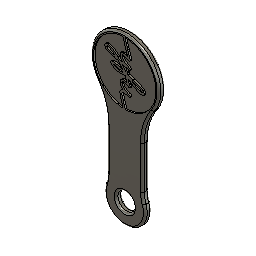
YFU-Einkaufswagenlöser (Autodesk Fusion 360 design; units mm, degrees)
Autodesk Fusion 360 part; units mm, degrees
sketch "Skizze1" plane through (0, 0, 0) normal (0, 0, 1) x (1, 0, 0)
  circle A0 centre (0, 0) radius 11.625
  line L0 (0, 0) -> (0, -38) construction
  circle A1 centre (0, -38) radius 7
  line L1 (6, -38) -> (-6, -38) construction
  line L2 (-6, -38) -> (-6, 0)
  line L3 (-6, 0) -> (6, 0) construction
  line L4 (6, 0) -> (6, -38)
  line L5 (6, -38) -> (-6, 0) construction
  line L6 (-6, -38) -> (6, 0) construction
  circle A2 centre (0, -38) radius 3
  point P0 (0, -19)
  dimension "d1" = 23.25
  dimension "d2" = 38
  dimension "d3" = 14
  dimension "d4" = 12
  dimension "d5" = 38
  dimension "d6" = 6
  constraint coincident A0.centre L0.start
  constraint vertical L0
  constraint coincident L0.end A1.centre
  constraint horizontal L1
  constraint perpendicular L1 L2
  constraint parallel L1 L3
  constraint parallel L2 L4
  constraint coincident L5 P0
  constraint coincident L6 P0
  constraint midpoint L0 P0
  constraint concentric A1 A2
  measures "d1" diameter of A0
  measures "d2" distance of A0.centre L0.end
  measures "d3" diameter of A1
  measures "d4" distance of L2.end L3.end
  measures "d5" distance of L1.end L2.end
  measures "d6" diameter of A2
extrude "Extrusion1" add sketch "Skizze1" along normal blind 2.2
fillet "Abrundung1" radius 20 2 edges at (6, -9.9569, 1.1) (-6, -9.9569, 1.1)
fillet "Abrundung2" radius 10 2 edges at (-6, -34.3944, 1.1) (6, -34.3944, 1.1)
fillet "Abrundung3" radius 0.65 18 edges at (-2.797, -36.9152, 0) (-2.797, -36.9152, 2.2) (6.1482, -33.9704, 0) (0, -45, 0) (-6.1482, -33.9704, 0) (-6, -25.1297, 0) (-6.91, -12.0396, 0) (0, 11.625, 0) (6.91, -12.0396, 0) (6, -25.1297, 0) (6.91, -12.0396, 2.2) (0, 11.625, 2.2) (-6.91, -12.0396, 2.2) (-6, -25.1297, 2.2) (-6.1482, -33.9704, 2.2) (0, -45, 2.2) (6.1482, -33.9704, 2.2) (6, -25.1297, 2.2)
sketch "Skizze2" plane through (0, 0, 2.2) normal (0, 0, 1) x (1, 0, 0)
  spline S0 degree 3 poles (-10.5033, 1.5521) (-10.1528, 3.8406) (-9.1449, 5.8129) (-7.4734, 7.4809) knots 0 0 0 0 1 1 1 1
  spline S1 degree 3 poles (-7.4734, 7.4809) (-5.8523, 9.0987) (-4.0263, 10.0374) (-1.7058, 10.4458) knots 0 0 0 0 1 1 1 1
  spline S2 degree 3 poles (-1.7058, 10.4458) (-0.9378, 10.5809) (-0.7066, 10.5692) (-0.6295, 10.3913) knots 0 0 0 0 1 1 1 1
  spline S3 degree 3 poles (-0.6295, 10.3913) (-0.4704, 10.0242) (0.9325, 5.5157) (0.9027, 5.4675) knots 0 0 0 0 1 1 1 1
  spline S4 degree 3 poles (0.9027, 5.4675) (0.8842, 5.4377) (0.6417, 5.4858) (0.3637, 5.5744) knots 0 0 0 0 1 1 1 1
  spline S5 degree 3 poles (0.3637, 5.5744) (-0.0376, 5.7023) (-0.2457, 5.731) (-0.646, 5.7135) knots 0 0 0 0 1 1 1 1
  spline S6 degree 3 poles (-0.646, 5.7135) (-1.1144, 5.693) (-1.1653, 5.6764) (-1.3616, 5.4806) knots 0 0 0 0 1 1 1 1
  spline S7 degree 3 poles (-1.3616, 5.4806) (-1.5554, 5.2872) (-1.575, 5.2295) (-1.5974, 4.7865) knots 0 0 0 0 1 1 1 1
  spline S8 degree 3 poles (-1.5974, 4.7865) (-1.6181, 4.3785) (-1.5968, 4.2494) (-1.462, 3.9572) knots 0 0 0 0 1 1 1 1
  spline S9 degree 3 poles (-1.462, 3.9572) (-1.3741, 3.7669) (-1.1921, 3.4804) (-1.0575, 3.3207) knots 0 0 0 0 1 1 1 1
  spline S10 degree 3 poles (-1.0575, 3.3207) (-0.9166, 3.1535) (-0.8445, 3.0197) (-0.8876, 3.0053) knots 0 0 0 0 1 1 1 1
  spline S11 degree 3 poles (-0.8876, 3.0053) (-0.9287, 2.9917) (-1.159, 3.0334) (-1.3993, 3.098) knots 0 0 0 0 1 1 1 1
  spline S12 degree 3 poles (-1.3993, 3.098) (-1.7925, 3.2038) (-1.8915, 3.2678) (-2.3902, 3.7386) knots 0 0 0 0 1 1 1 1
  spline S13 degree 3 poles (-2.3902, 3.7386) (-3.7693, 5.0406) (-4.966, 5.7252) (-5.862, 5.7247) knots 0 0 0 0 1 1 1 1
  spline S14 degree 3 poles (-5.862, 5.7247) (-6.5411, 5.7242) (-6.8964, 5.3636) (-6.8002, 4.7721) knots 0 0 0 0 1 1 1 1
  spline S15 degree 3 poles (-6.8002, 4.7721) (-6.6703, 3.9732) (-5.9098, 3.5452) (-3.6346, 2.9902) knots 0 0 0 0 1 1 1 1
  line L0 (-3.6346, 2.9902) -> (-2.2924, 2.6628)
  line L1 (-2.2924, 2.6628) -> (-1.8961, 2.2472)
  spline S16 degree 3 poles (-1.8961, 2.2472) (-1.2636, 1.5837) (-0.7353, 0.9112) (-0.7998, 0.8515) knots 0 0 0 0 1 1 1 1
  spline S17 degree 3 poles (-0.7998, 0.8515) (-0.8322, 0.8215) (-1.1959, 0.8969) (-1.6081, 1.0189) knots 0 0 0 0 1 1 1 1
  spline S18 degree 3 poles (-1.6081, 1.0189) (-3.5379, 1.5902) (-4.6198, 1.6409) (-4.7704, 1.1673) knots 0 0 0 0 1 1 1 1
  spline S19 degree 3 poles (-4.7704, 1.1673) (-4.9604, 0.5698) (-4.1022, -0.1345) (-2.6696, -0.5565) knots 0 0 0 0 1 1 1 1
  spline S20 degree 3 poles (-2.6696, -0.5565) (-1.9152, -0.7788) (-0.8863, -0.8349) (-0.3699, -0.6819) knots 0 0 0 0 1 1 1 1
  spline S21 degree 3 poles (-0.3699, -0.6819) (0.2499, -0.4983) (0.2219, -0.4822) (0.357, -1.1032) knots 0 0 0 0 1 1 1 1
  spline S22 degree 3 poles (0.357, -1.1032) (0.4231, -1.4067) (0.5242, -1.7964) (0.5816, -1.9691) knots 0 0 0 0 1 1 1 1
  spline S23 degree 3 poles (0.5816, -1.9691) (0.6391, -2.1419) (0.6693, -2.3) (0.6487, -2.3206) knots 0 0 0 0 1 1 1 1
  spline S24 degree 3 poles (0.6487, -2.3206) (0.6281, -2.3411) (0.4399, -2.3099) (0.2305, -2.2513) knots 0 0 0 0 1 1 1 1
  spline S25 degree 3 poles (0.2305, -2.2513) (-0.5621, -2.0293) (-1.1647, -2.1532) (-1.4656, -2.5999) knots 0 0 0 0 1 1 1 1
  spline S26 degree 3 poles (-1.4656, -2.5999) (-1.601, -2.8011) (-1.6163, -2.8882) (-1.5965, -3.3479) knots 0 0 0 0 1 1 1 1
  spline S27 degree 3 poles (-1.5965, -3.3479) (-1.5696, -3.9746) (-1.4152, -4.3304) (-0.9494, -4.839) knots 0 0 0 0 1 1 1 1
  spline S28 degree 3 poles (-0.9494, -4.839) (-0.774, -5.0305) (-0.6306, -5.2039) (-0.6306, -5.2243) knots 0 0 0 0 1 1 1 1
  spline S29 degree 3 poles (-0.6306, -5.2243) (-0.6306, -5.2448) (-0.7502, -5.2936) (-0.8965, -5.3329) knots 0 0 0 0 1 1 1 1
  spline S30 degree 3 poles (-0.8965, -5.3329) (-1.0427, -5.3722) (-1.2684, -5.5013) (-1.3979, -5.6198) knots 0 0 0 0 1 1 1 1
  spline S31 degree 3 poles (-1.3979, -5.6198) (-1.6136, -5.8171) (-1.6354, -5.8701) (-1.6574, -6.25) knots 0 0 0 0 1 1 1 1
  spline S32 degree 3 poles (-1.6574, -6.25) (-1.6842, -6.7123) (-1.4917, -7.4945) (-0.8791, -9.4137) knots 0 0 0 0 1 1 1 1
  spline S33 degree 3 poles (-0.8791, -9.4137) (-0.6741, -10.056) (-0.5653, -10.4935) (-0.6023, -10.5272) knots 0 0 0 0 1 1 1 1
  spline S34 degree 3 poles (-0.6023, -10.5272) (-0.6902, -10.6076) (-1.662, -10.4904) (-2.4376, -10.306) knots 0 0 0 0 1 1 1 1
  spline S35 degree 3 poles (-2.4376, -10.306) (-4.4197, -9.8347) (-6.0019, -8.9472) (-7.4774, -7.4792) knots 0 0 0 0 1 1 1 1
  spline S36 degree 3 poles (-7.4774, -7.4792) (-9.0145, -5.9499) (-9.9528, -4.2259) (-10.4098, -2.0912) knots 0 0 0 0 1 1 1 1
  spline S37 degree 3 poles (-10.4098, -2.0912) (-10.5887, -1.2553) (-10.6382, 0.6718) (-10.5033, 1.5521) knots 0 0 0 0 1 1 1 1
  spline S38 degree 3 poles (-6.0043, 5.0521) (-5.6966, 5.1699) (-4.6934, 4.7348) (-3.9256, 4.1504) knots 0 0 0 0 1 1 1 1
  spline S39 degree 3 poles (-3.9256, 4.1504) (-3.1644, 3.571) (-3.2537, 3.5349) (-4.5072, 3.9149) knots 0 0 0 0 1 1 1 1
  spline S40 degree 3 poles (-4.5072, 3.9149) (-5.2149, 4.1295) (-5.7283, 4.3623) (-5.9582, 4.5727) knots 0 0 0 0 1 1 1 1
  spline S41 degree 3 poles (-5.9582, 4.5727) (-6.1266, 4.7269) (-6.1524, 4.9953) (-6.0043, 5.0521) knots 0 0 0 0 1 1 1 1
  spline S42 degree 3 poles (-3.7885, 0.7956) (-3.7056, 0.8784) (-1.0857, 0.2309) (-0.8238, 0.0629) knots 0 0 0 0 1 1 1 1
  spline S43 degree 3 poles (-0.8238, 0.0629) (-0.7402, 0.0092) (-0.7405, -0.0064) (-0.826, -0.0625) knots 0 0 0 0 1 1 1 1
  spline S44 degree 3 poles (-0.826, -0.0625) (-1.1352, -0.265) (-2.5574, 0.022) (-3.4491, 0.4669) knots 0 0 0 0 1 1 1 1
  spline S45 degree 3 poles (-3.4491, 0.4669) (-3.8015, 0.6427) (-3.8727, 0.7116) (-3.7885, 0.7956) knots 0 0 0 0 1 1 1 1
  spline S46 degree 3 poles (-0.8861, -6.0748) (-0.6864, -5.8945) (0.0147, -5.9197) (0.8864, -6.1385) knots 0 0 0 0 1 1 1 1
  spline S47 degree 3 poles (0.8864, -6.1385) (1.6494, -6.3301) (1.8242, -6.3185) (1.8861, -6.0725) knots 0 0 0 0 1 1 1 1
  spline S48 degree 3 poles (1.8861, -6.0725) (1.9422, -5.8496) (1.7868, -5.6991) (1.3212, -5.5254) knots 0 0 0 0 1 1 1 1
  spline S49 degree 3 poles (1.3212, -5.5254) (0.0512, -5.0514) (-0.9539, -4.056) (-0.9557, -3.2703) knots 0 0 0 0 1 1 1 1
  spline S50 degree 3 poles (-0.9557, -3.2703) (-0.9565, -2.9578) (-0.7938, -2.795) (-0.4809, -2.795) knots 0 0 0 0 1 1 1 1
  spline S51 degree 3 poles (-0.4809, -2.795) (-0.2386, -2.795) (0.5756, -3.0693) (1.0649, -3.3158) knots 0 0 0 0 1 1 1 1
  spline S52 degree 3 poles (1.0649, -3.3158) (1.5475, -3.559) (1.7577, -3.5672) (1.8583, -3.3468) knots 0 0 0 0 1 1 1 1
  spline S53 degree 3 poles (1.8583, -3.3468) (1.924, -3.2028) (1.8969, -3.1144) (1.634, -2.6151) knots 0 0 0 0 1 1 1 1
  spline S54 degree 3 poles (1.634, -2.6151) (1.29, -1.9614) (1.031, -1.2409) (1.1114, -1.1607) knots 0 0 0 0 1 1 1 1
  spline S55 degree 3 poles (1.1114, -1.1607) (1.1417, -1.1305) (1.4293, -1.2975) (1.7506, -1.5319) knots 0 0 0 0 1 1 1 1
  spline S56 degree 3 poles (1.7506, -1.5319) (2.874, -2.3516) (4.2521, -3.1185) (5.1301, -3.4126) knots 0 0 0 0 1 1 1 1
  spline S57 degree 3 poles (5.1301, -3.4126) (5.9218, -3.6779) (6.3774, -3.6152) (6.5677, -3.2152) knots 0 0 0 0 1 1 1 1
  spline S58 degree 3 poles (6.5677, -3.2152) (6.769, -2.7918) (6.6487, -2.4444) (6.1439, -1.9915) knots 0 0 0 0 1 1 1 1
  spline S59 degree 3 poles (6.1439, -1.9915) (5.6694, -1.5657) (4.7908, -1.1557) (2.9213, -0.4876) knots 0 0 0 0 1 1 1 1
  spline S60 degree 3 poles (2.9213, -0.4876) (2.061, -0.1801) (1.275, 0.1038) (1.1744, 0.1434) knots 0 0 0 0 1 1 1 1
  spline S61 degree 3 poles (1.1744, 0.1434) (0.9982, 0.2128) (0.9932, 0.2274) (1.0339, 0.553) knots 0 0 0 0 1 1 1 1
  spline S62 degree 3 poles (1.0339, 0.553) (1.0675, 0.8209) (1.0538, 0.9129) (0.9676, 0.9989) knots 0 0 0 0 1 1 1 1
  spline S63 degree 3 poles (0.9676, 0.9989) (0.8043, 1.1619) (0.6351, 1.1301) (0.457, 0.903) knots 0 0 0 0 1 1 1 1
  line L2 (0.457, 0.903) -> (0.2968, 0.6988)
  line L3 (0.2968, 0.6988) -> (0.1663, 0.8542)
  spline S64 degree 3 poles (0.1663, 0.8542) (-0.2998, 1.4091) (-0.8261, 2.0959) (-0.8261, 2.1495) knots 0 0 0 0 1 1 1 1
  spline S65 degree 3 poles (-0.8261, 2.1495) (-0.8261, 2.2398) (-0.8411, 2.2428) (0.392, 1.9123) knots 0 0 0 0 1 1 1 1
  spline S66 degree 3 poles (0.392, 1.9123) (1.6018, 1.588) (1.8152, 1.5801) (1.8848, 1.857) knots 0 0 0 0 1 1 1 1
  spline S67 degree 3 poles (1.8848, 1.857) (1.9425, 2.0863) (1.8472, 2.1729) (1.1356, 2.5387) knots 0 0 0 0 1 1 1 1
  spline S68 degree 3 poles (1.1356, 2.5387) (-0.0871, 3.1671) (-0.8665, 3.933) (-0.9393, 4.5777) knots 0 0 0 0 1 1 1 1
  spline S69 degree 3 poles (-0.9393, 4.5777) (-0.9609, 4.7693) (-0.9437, 4.9139) (-0.8917, 4.9764) knots 0 0 0 0 1 1 1 1
  spline S70 degree 3 poles (-0.8917, 4.9764) (-0.7063, 5.1993) (0.1479, 5.0127) (1.0783, 4.5461) knots 0 0 0 0 1 1 1 1
  spline S71 degree 3 poles (1.0783, 4.5461) (1.5402, 4.3145) (1.7588, 4.3049) (1.8534, 4.5121) knots 0 0 0 0 1 1 1 1
  spline S72 degree 3 poles (1.8534, 4.5121) (1.9121, 4.6405) (1.7853, 5.098) (1.0653, 7.3575) knots 0 0 0 0 1 1 1 1
  spline S73 degree 3 poles (1.0653, 7.3575) (0.5934, 8.8383) (0.1769, 10.1477) (0.1398, 10.2673) knots 0 0 0 0 1 1 1 1
  spline S74 degree 3 poles (0.1398, 10.2673) (0.0361, 10.6011) (0.101, 10.6227) (0.9537, 10.5389) knots 0 0 0 0 1 1 1 1
  spline S75 degree 3 poles (0.9537, 10.5389) (3.6317, 10.2757) (5.8072, 9.2204) (7.6787, 7.277) knots 0 0 0 0 1 1 1 1
  spline S76 degree 3 poles (7.6787, 7.277) (9.1937, 5.7038) (10.122, 3.8436) (10.4818, 1.66) knots 0 0 0 0 1 1 1 1
  spline S77 degree 3 poles (10.4818, 1.66) (10.6245, 0.7945) (10.6099, -0.9093) (10.4521, -1.8307) knots 0 0 0 0 1 1 1 1
  spline S78 degree 3 poles (10.4521, -1.8307) (9.7041, -6.1971) (6.1688, -9.7165) (1.8134, -10.4307) knots 0 0 0 0 1 1 1 1
  spline S79 degree 3 poles (1.8134, -10.4307) (0.8283, -10.5922) (0.3166, -10.6224) (0.2362, -10.5236) knots 0 0 0 0 1 1 1 1
  spline S80 degree 3 poles (0.2362, -10.5236) (0.0663, -10.3148) (-1.0208, -6.6927) (-1.0213, -6.3334) knots 0 0 0 0 1 1 1 1
  spline S81 degree 3 poles (-1.0213, -6.3334) (-1.0213, -6.2585) (-0.9606, -6.1421) (-0.8861, -6.0748) knots 0 0 0 0 1 1 1 1
  spline S82 degree 3 poles (2.5139, -1.0726) (2.8094, -1.1579) (4.268, -1.7013) (4.632, -1.8617) knots 0 0 0 0 1 1 1 1
  spline S83 degree 3 poles (4.632, -1.8617) (5.1094, -2.0721) (5.8604, -2.5681) (5.9145, -2.7089) knots 0 0 0 0 1 1 1 1
  spline S84 degree 3 poles (5.9145, -2.7089) (5.9373, -2.7682) (5.9281, -2.8447) (5.8939, -2.8787) knots 0 0 0 0 1 1 1 1
  spline S85 degree 3 poles (5.8939, -2.8787) (5.7345, -3.0378) (4.127, -2.3053) (2.9928, -1.5568) knots 0 0 0 0 1 1 1 1
  spline S86 degree 3 poles (2.9928, -1.5568) (2.3828, -1.1542) (2.2174, -0.987) (2.5139, -1.0726) knots 0 0 0 0 1 1 1 1
  circle A0 centre (0, -38) radius 3.65
  arc A1 (9.0229, -6.248) -> (5.35, -18.0039) centre (26, -18.0039) ccw
  arc A2 (9.0229, -6.248) -> (-9.0229, -6.248) centre (0, 0) ccw
  arc A3 (-5.35, -18.0039) -> (-9.0229, -6.248) centre (-26, -18.0039) ccw
  line L4 (-5.35, -18.0039) -> (-5.35, -32.2554)
  arc A4 (-5.9765, -35.8542) -> (-5.35, -32.2554) centre (-16, -32.2554) ccw
  arc A5 (-5.9765, -35.8542) -> (5.9765, -35.8542) centre (0, -38) ccw
  arc A6 (5.35, -32.2554) -> (5.9765, -35.8542) centre (16, -32.2554) ccw
  line L5 (5.35, -32.2554) -> (5.35, -18.0039)
extrude "Extrusion2" cut sketch "Skizze2" against normal blind 0.5 contours S0 S1 S2 S3 S4 S5 S6 S7 S8 S9 S10 S11 S12 S13 S14 S15 L0 L1 S16 S17 S18 S19 S20 S21 S22 S23 S24 S25 S26 S27 S28 S29 S30 S31 S32 S33 S34 S35 S36 S37 | S38 S39 S40 S41 | S42 S43 S44 S45 | S46 S47 S48 S49 S50 S51 S52 S53 S54 S55 S56 S57 S58 S59 S60 S61 S62 S63 L2 L3 S64 S65 S66 S67 S68 S69 S70 S71 S72 S73 S74 S75 S76 S77 S78 S79 S80 S81 | S82 S83 S84 S85 S86
sketch "Skizze3" plane through (0, 0, 0) normal (0, 0, -1) x (-1, 0, 0)
  spline S0 degree 3 poles (-10.5497, 1.559) (-10.1976, 3.8576) (-9.1852, 5.8385) (-7.5064, 7.5139) knots 0 0 0 0 1 1 1 1
  spline S1 degree 3 poles (-7.5064, 7.5139) (-5.8781, 9.1389) (-4.0441, 10.0817) (-1.7134, 10.4918) knots 0 0 0 0 1 1 1 1
  spline S2 degree 3 poles (-1.7134, 10.4918) (-0.9419, 10.6276) (-0.7097, 10.6158) (-0.6323, 10.4372) knots 0 0 0 0 1 1 1 1
  spline S3 degree 3 poles (-0.6323, 10.4372) (-0.4725, 10.0685) (0.9366, 5.54) (0.9067, 5.4916) knots 0 0 0 0 1 1 1 1
  spline S4 degree 3 poles (0.9067, 5.4916) (0.8881, 5.4617) (0.6445, 5.51) (0.3653, 5.599) knots 0 0 0 0 1 1 1 1
  spline S5 degree 3 poles (0.3653, 5.599) (-0.0378, 5.7274) (-0.2467, 5.7563) (-0.6489, 5.7387) knots 0 0 0 0 1 1 1 1
  spline S6 degree 3 poles (-0.6489, 5.7387) (-1.1193, 5.7182) (-1.1705, 5.7015) (-1.3677, 5.5047) knots 0 0 0 0 1 1 1 1
  spline S7 degree 3 poles (-1.3677, 5.5047) (-1.5623, 5.3105) (-1.5819, 5.2526) (-1.6045, 4.8076) knots 0 0 0 0 1 1 1 1
  spline S8 degree 3 poles (-1.6045, 4.8076) (-1.6252, 4.3978) (-1.6038, 4.2682) (-1.4685, 3.9747) knots 0 0 0 0 1 1 1 1
  spline S9 degree 3 poles (-1.4685, 3.9747) (-1.3802, 3.7835) (-1.1974, 3.4958) (-1.0622, 3.3353) knots 0 0 0 0 1 1 1 1
  spline S10 degree 3 poles (-1.0622, 3.3353) (-0.9207, 3.1674) (-0.8483, 3.033) (-0.8915, 3.0186) knots 0 0 0 0 1 1 1 1
  spline S11 degree 3 poles (-0.8915, 3.0186) (-0.9328, 3.0049) (-1.1641, 3.0468) (-1.4055, 3.1117) knots 0 0 0 0 1 1 1 1
  spline S12 degree 3 poles (-1.4055, 3.1117) (-1.8004, 3.2179) (-1.8999, 3.2822) (-2.4007, 3.7551) knots 0 0 0 0 1 1 1 1
  spline S13 degree 3 poles (-2.4007, 3.7551) (-3.7859, 5.0628) (-4.9879, 5.7504) (-5.8878, 5.7499) knots 0 0 0 0 1 1 1 1
  spline S14 degree 3 poles (-5.8878, 5.7499) (-6.57, 5.7495) (-6.9268, 5.3872) (-6.8302, 4.7932) knots 0 0 0 0 1 1 1 1
  spline S15 degree 3 poles (-6.8302, 4.7932) (-6.6997, 3.9908) (-5.9359, 3.5608) (-3.6506, 3.0033) knots 0 0 0 0 1 1 1 1
  line L0 (-3.6506, 3.0033) -> (-2.3025, 2.6745)
  line L1 (-2.3025, 2.6745) -> (-1.9045, 2.2571)
  spline S16 degree 3 poles (-1.9045, 2.2571) (-1.2692, 1.5907) (-0.7385, 0.9152) (-0.8034, 0.8552) knots 0 0 0 0 1 1 1 1
  spline S17 degree 3 poles (-0.8034, 0.8552) (-0.8359, 0.8252) (-1.2012, 0.9008) (-1.6152, 1.0234) knots 0 0 0 0 1 1 1 1
  spline S18 degree 3 poles (-1.6152, 1.0234) (-3.5535, 1.5972) (-4.6402, 1.6482) (-4.7915, 1.1724) knots 0 0 0 0 1 1 1 1
  spline S19 degree 3 poles (-4.7915, 1.1724) (-4.9823, 0.5723) (-4.1203, -0.135) (-2.6814, -0.559) knots 0 0 0 0 1 1 1 1
  spline S20 degree 3 poles (-2.6814, -0.559) (-1.9236, -0.7822) (-0.8902, -0.8386) (-0.3715, -0.685) knots 0 0 0 0 1 1 1 1
  spline S21 degree 3 poles (-0.3715, -0.685) (0.251, -0.5005) (0.2229, -0.4843) (0.3586, -1.1081) knots 0 0 0 0 1 1 1 1
  spline S22 degree 3 poles (0.3586, -1.1081) (0.425, -1.4129) (0.5265, -1.8044) (0.5842, -1.9778) knots 0 0 0 0 1 1 1 1
  spline S23 degree 3 poles (0.5842, -1.9778) (0.6419, -2.1513) (0.6723, -2.3102) (0.6516, -2.3308) knots 0 0 0 0 1 1 1 1
  spline S24 degree 3 poles (0.6516, -2.3308) (0.6309, -2.3514) (0.4418, -2.3201) (0.2315, -2.2612) knots 0 0 0 0 1 1 1 1
  spline S25 degree 3 poles (0.2315, -2.2612) (-0.5646, -2.0383) (-1.1698, -2.1627) (-1.472, -2.6114) knots 0 0 0 0 1 1 1 1
  spline S26 degree 3 poles (-1.472, -2.6114) (-1.6081, -2.8134) (-1.6234, -2.9009) (-1.6036, -3.3626) knots 0 0 0 0 1 1 1 1
  spline S27 degree 3 poles (-1.6036, -3.3626) (-1.5765, -3.9921) (-1.4215, -4.3495) (-0.9536, -4.8603) knots 0 0 0 0 1 1 1 1
  spline S28 degree 3 poles (-0.9536, -4.8603) (-0.7774, -5.0527) (-0.6333, -5.2268) (-0.6333, -5.2474) knots 0 0 0 0 1 1 1 1
  spline S29 degree 3 poles (-0.6333, -5.2474) (-0.6333, -5.2679) (-0.7535, -5.317) (-0.9004, -5.3564) knots 0 0 0 0 1 1 1 1
  spline S30 degree 3 poles (-0.9004, -5.3564) (-1.0473, -5.3959) (-1.2739, -5.5256) (-1.4041, -5.6446) knots 0 0 0 0 1 1 1 1
  spline S31 degree 3 poles (-1.4041, -5.6446) (-1.6207, -5.8427) (-1.6427, -5.896) (-1.6648, -6.2776) knots 0 0 0 0 1 1 1 1
  spline S32 degree 3 poles (-1.6648, -6.2776) (-1.6916, -6.7419) (-1.4983, -7.5275) (-0.883, -9.4552) knots 0 0 0 0 1 1 1 1
  spline S33 degree 3 poles (-0.883, -9.4552) (-0.6771, -10.1004) (-0.5678, -10.5398) (-0.6049, -10.5737) knots 0 0 0 0 1 1 1 1
  spline S34 degree 3 poles (-0.6049, -10.5737) (-0.6932, -10.6544) (-1.6693, -10.5367) (-2.4483, -10.3515) knots 0 0 0 0 1 1 1 1
  spline S35 degree 3 poles (-2.4483, -10.3515) (-4.4392, -9.878) (-6.0284, -8.9867) (-7.5104, -7.5122) knots 0 0 0 0 1 1 1 1
  spline S36 degree 3 poles (-7.5104, -7.5122) (-9.0543, -5.9761) (-9.9967, -4.2445) (-10.4557, -2.1004) knots 0 0 0 0 1 1 1 1
  spline S37 degree 3 poles (-10.4557, -2.1004) (-10.6354, -1.2608) (-10.6851, 0.6748) (-10.5497, 1.559) knots 0 0 0 0 1 1 1 1
  spline S38 degree 3 poles (-6.0308, 5.0744) (-5.7217, 5.1927) (-4.7141, 4.7557) (-3.9429, 4.1687) knots 0 0 0 0 1 1 1 1
  spline S39 degree 3 poles (-3.9429, 4.1687) (-3.1783, 3.5868) (-3.268, 3.5505) (-4.527, 3.9322) knots 0 0 0 0 1 1 1 1
  spline S40 degree 3 poles (-4.527, 3.9322) (-5.2379, 4.1477) (-5.7536, 4.3815) (-5.9845, 4.5929) knots 0 0 0 0 1 1 1 1
  spline S41 degree 3 poles (-5.9845, 4.5929) (-6.1536, 4.7477) (-6.1795, 5.0174) (-6.0308, 5.0744) knots 0 0 0 0 1 1 1 1
  spline S42 degree 3 poles (-3.8052, 0.7991) (-3.7219, 0.8823) (-1.0905, 0.2319) (-0.8274, 0.0631) knots 0 0 0 0 1 1 1 1
  spline S43 degree 3 poles (-0.8274, 0.0631) (-0.7434, 0.0092) (-0.7437, -0.0064) (-0.8297, -0.0627) knots 0 0 0 0 1 1 1 1
  spline S44 degree 3 poles (-0.8297, -0.0627) (-1.1402, -0.2662) (-2.5687, 0.0221) (-3.4643, 0.4689) knots 0 0 0 0 1 1 1 1
  spline S45 degree 3 poles (-3.4643, 0.4689) (-3.8183, 0.6455) (-3.8898, 0.7148) (-3.8052, 0.7991) knots 0 0 0 0 1 1 1 1
  spline S46 degree 3 poles (-0.89, -6.1016) (-0.6894, -5.9205) (0.0148, -5.9458) (0.8903, -6.1656) knots 0 0 0 0 1 1 1 1
  spline S47 degree 3 poles (0.8903, -6.1656) (1.6567, -6.358) (1.8323, -6.3464) (1.8944, -6.0993) knots 0 0 0 0 1 1 1 1
  spline S48 degree 3 poles (1.8944, -6.0993) (1.9507, -5.8755) (1.7947, -5.7242) (1.327, -5.5497) knots 0 0 0 0 1 1 1 1
  spline S49 degree 3 poles (1.327, -5.5497) (0.0514, -5.0737) (-0.9581, -4.0738) (-0.96, -3.2847) knots 0 0 0 0 1 1 1 1
  spline S50 degree 3 poles (-0.96, -3.2847) (-0.9607, -2.9708) (-0.7973, -2.8074) (-0.483, -2.8074) knots 0 0 0 0 1 1 1 1
  spline S51 degree 3 poles (-0.483, -2.8074) (-0.2396, -2.8074) (0.5781, -3.0829) (1.0696, -3.3305) knots 0 0 0 0 1 1 1 1
  spline S52 degree 3 poles (1.0696, -3.3305) (1.5544, -3.5747) (1.7654, -3.5829) (1.8665, -3.3615) knots 0 0 0 0 1 1 1 1
  spline S53 degree 3 poles (1.8665, -3.3615) (1.9325, -3.217) (1.9053, -3.1282) (1.6412, -2.6266) knots 0 0 0 0 1 1 1 1
  spline S54 degree 3 poles (1.6412, -2.6266) (1.2956, -1.9701) (1.0356, -1.2464) (1.1163, -1.1659) knots 0 0 0 0 1 1 1 1
  spline S55 degree 3 poles (1.1163, -1.1659) (1.1468, -1.1355) (1.4357, -1.3033) (1.7583, -1.5387) knots 0 0 0 0 1 1 1 1
  spline S56 degree 3 poles (1.7583, -1.5387) (2.8867, -2.362) (4.2709, -3.1323) (5.1528, -3.4277) knots 0 0 0 0 1 1 1 1
  spline S57 degree 3 poles (5.1528, -3.4277) (5.9479, -3.6941) (6.4056, -3.6312) (6.5967, -3.2294) knots 0 0 0 0 1 1 1 1
  spline S58 degree 3 poles (6.5967, -3.2294) (6.7988, -2.8042) (6.678, -2.4552) (6.1711, -2.0003) knots 0 0 0 0 1 1 1 1
  spline S59 degree 3 poles (6.1711, -2.0003) (5.6944, -1.5726) (4.8119, -1.1608) (2.9342, -0.4897) knots 0 0 0 0 1 1 1 1
  spline S60 degree 3 poles (2.9342, -0.4897) (2.0701, -0.1809) (1.2806, 0.1042) (1.1796, 0.144) knots 0 0 0 0 1 1 1 1
  spline S61 degree 3 poles (1.1796, 0.144) (1.0026, 0.2137) (0.9976, 0.2284) (1.0385, 0.5554) knots 0 0 0 0 1 1 1 1
  spline S62 degree 3 poles (1.0385, 0.5554) (1.0722, 0.8245) (1.0585, 0.9169) (0.9719, 1.0033) knots 0 0 0 0 1 1 1 1
  spline S63 degree 3 poles (0.9719, 1.0033) (0.8078, 1.167) (0.638, 1.1351) (0.459, 0.907) knots 0 0 0 0 1 1 1 1
  line L2 (0.459, 0.907) -> (0.2982, 0.7019)
  line L3 (0.2982, 0.7019) -> (0.167, 0.858)
  spline S64 degree 3 poles (0.167, 0.858) (-0.3012, 1.4153) (-0.8297, 2.1051) (-0.8297, 2.159) knots 0 0 0 0 1 1 1 1
  spline S65 degree 3 poles (-0.8297, 2.159) (-0.8297, 2.2497) (-0.8448, 2.2527) (0.3937, 1.9207) knots 0 0 0 0 1 1 1 1
  spline S66 degree 3 poles (0.3937, 1.9207) (1.6088, 1.5951) (1.8232, 1.5871) (1.8931, 1.8652) knots 0 0 0 0 1 1 1 1
  spline S67 degree 3 poles (1.8931, 1.8652) (1.9511, 2.0955) (1.8554, 2.1825) (1.1406, 2.5499) knots 0 0 0 0 1 1 1 1
  spline S68 degree 3 poles (1.1406, 2.5499) (-0.0875, 3.181) (-0.8703, 3.9504) (-0.9434, 4.5979) knots 0 0 0 0 1 1 1 1
  spline S69 degree 3 poles (-0.9434, 4.5979) (-0.9652, 4.7903) (-0.9478, 4.9356) (-0.8956, 4.9984) knots 0 0 0 0 1 1 1 1
  spline S70 degree 3 poles (-0.8956, 4.9984) (-0.7094, 5.2223) (0.1485, 5.0348) (1.0831, 4.5662) knots 0 0 0 0 1 1 1 1
  spline S71 degree 3 poles (1.0831, 4.5662) (1.547, 4.3335) (1.7666, 4.3239) (1.8616, 4.532) knots 0 0 0 0 1 1 1 1
  spline S72 degree 3 poles (1.8616, 4.532) (1.9205, 4.661) (1.7932, 5.1205) (1.07, 7.39) knots 0 0 0 0 1 1 1 1
  spline S73 degree 3 poles (1.07, 7.39) (0.5961, 8.8773) (0.1777, 10.1925) (0.1404, 10.3126) knots 0 0 0 0 1 1 1 1
  spline S74 degree 3 poles (0.1404, 10.3126) (0.0363, 10.6478) (0.1014, 10.6696) (0.9579, 10.5854) knots 0 0 0 0 1 1 1 1
  spline S75 degree 3 poles (0.9579, 10.5854) (3.6477, 10.321) (5.8329, 9.2611) (7.7126, 7.3091) knots 0 0 0 0 1 1 1 1
  spline S76 degree 3 poles (7.7126, 7.3091) (9.2342, 5.729) (10.1667, 3.8605) (10.5281, 1.6674) knots 0 0 0 0 1 1 1 1
  spline S77 degree 3 poles (10.5281, 1.6674) (10.6713, 0.798) (10.6568, -0.9134) (10.4982, -1.8388) knots 0 0 0 0 1 1 1 1
  spline S78 degree 3 poles (10.4982, -1.8388) (9.7469, -6.2244) (6.1961, -9.7594) (1.8214, -10.4767) knots 0 0 0 0 1 1 1 1
  spline S79 degree 3 poles (1.8214, -10.4767) (0.832, -10.6389) (0.318, -10.6692) (0.2372, -10.5701) knots 0 0 0 0 1 1 1 1
  spline S80 degree 3 poles (0.2372, -10.5701) (0.0666, -10.3603) (-1.0253, -6.7222) (-1.0258, -6.3614) knots 0 0 0 0 1 1 1 1
  spline S81 degree 3 poles (-1.0258, -6.3614) (-1.0258, -6.2861) (-0.9648, -6.1692) (-0.89, -6.1016) knots 0 0 0 0 1 1 1 1
  spline S82 degree 3 poles (2.525, -1.0773) (2.8218, -1.163) (4.2868, -1.7088) (4.6524, -1.8699) knots 0 0 0 0 1 1 1 1
  spline S83 degree 3 poles (4.6524, -1.8699) (5.1319, -2.0812) (5.8862, -2.5795) (5.9406, -2.7208) knots 0 0 0 0 1 1 1 1
  spline S84 degree 3 poles (5.9406, -2.7208) (5.9635, -2.7804) (5.9542, -2.8572) (5.92, -2.8914) knots 0 0 0 0 1 1 1 1
  spline S85 degree 3 poles (5.92, -2.8914) (5.7598, -3.0512) (4.1453, -2.3155) (3.006, -1.5637) knots 0 0 0 0 1 1 1 1
  spline S86 degree 3 poles (3.006, -1.5637) (2.3933, -1.1593) (2.2272, -0.9914) (2.525, -1.0773) knots 0 0 0 0 1 1 1 1
  circle A0 centre (0, -38) radius 3.65
  arc A1 (-5.9765, -35.8542) -> (-5.35, -32.2554) centre (-16, -32.2554) ccw
  arc A2 (-5.9765, -35.8542) -> (5.9765, -35.8542) centre (0, -38) ccw
  arc A3 (5.35, -32.2554) -> (5.9765, -35.8542) centre (16, -32.2554) ccw
  line L4 (5.35, -32.2554) -> (5.35, -18.0039)
  arc A4 (9.0229, -6.248) -> (5.35, -18.0039) centre (26, -18.0039) ccw
  arc A5 (9.0229, -6.248) -> (-9.0229, -6.248) centre (0, 0) ccw
  arc A6 (-5.35, -18.0039) -> (-9.0229, -6.248) centre (-26, -18.0039) ccw
  line L5 (-5.35, -18.0039) -> (-5.35, -32.2554)
extrude "Extrusion3" [suppressed]
named bodies: "YFU-Einkaufswagenlöser"
